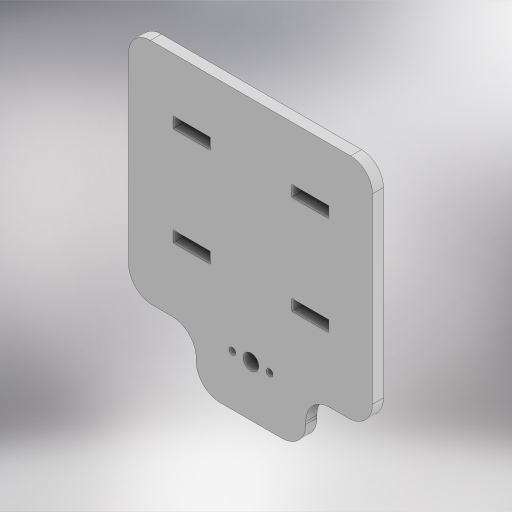
# Autodesk Inventor part: side
Saved by Autodesk Inventor 2023.5 (Build 275446000, 446)
## iProperties
Created: 2026-10-31
Part Number: side
Material: Generic
Document SubType Name: Modeling
Designer: WORKPLUS
Density: 1 g/cm^3
Appearance: Default
Author: WORKPLUS
Autodesk Inventor part; units mm, degrees
ref_plane "YZ Plane" through (0, 0, 0) normal (1, 0, 0) x (0, 1, 0)
ref_plane "XZ Plane" through (0, 0, 0) normal (0, 1, 0) x (-1, 0, 0)
ref_plane "XY Plane" through (0, 0, 0) normal (0, 0, 1) x (1, 0, 0)
sketch "Sketch1" plane through (0, 0, 0) normal (0, 0, 1) x (1, 0, 0)
  line L0 (-55.8711, -100) -> (55.3607, -100)
  line L1 (55.3607, -100) -> (55.3607, 27.1373)
  line L2 (-55.8711, 27.1373) -> (-55.8711, -100)
  line L3 (-35.4, -2.5) -> (35.4, -2.5)
  line L4 (35.4, -2.5) -> (35.4, 2.5)
  line L5 (35.4, 2.5) -> (-35.4, 2.5)
  line L6 (-35.4, 2.5) -> (-35.4, -2.5)
  line L7 (-35.4, 2.5) -> (-18.614, 2.5)
  line L8 (-18.614, 2.5) -> (-18.614, -2.5)
  line L9 (-18.614, -2.5) -> (-35.4, -2.5)
  line L10 (-35.4, -2.5) -> (-35.4, 2.5)
  line L11 (35.4, 2.5) -> (18.614, 2.5)
  line L12 (18.614, 2.5) -> (18.614, -2.5)
  line L13 (18.614, -2.5) -> (35.4, -2.5)
  line L14 (35.4, -2.5) -> (35.4, 2.5)
  line L15 (0, -2.5) -> (0, -42.5)
  line L16 (0, -42.5) -> (-35.4, -42.5)
  line L17 (0, -42.5) -> (35.4, -42.5)
  line L18 (-35.4, -42.5) -> (-35.4, -47.5)
  line L19 (-35.4, -47.5) -> (35.4, -47.5)
  line L20 (35.4, -47.5) -> (35.4, -42.5)
  line L21 (-18.614, -42.5) -> (-18.614, -47.5)
  line L22 (18.614, -42.5) -> (18.614, -47.5)
  line L23 (-55.8711, 27.1373) -> (55.3607, 27.1373)
  circle A0 centre (-8.5, -76.8807) radius 1.5
  circle A1 centre (8.5, -76.8807) radius 1.5
  circle A2 centre (0, -76.8807) radius 3.5
  circle A3 centre (0, -76.8807) radius 15
  line L24 (-55.8711, -76.8807) -> (-15, -76.8807)
  line L25 (15, -76.8807) -> (55.3607, -76.8807)
  line L26 (-25, -76.8807) -> (-25, -100)
  line L27 (25, -76.8807) -> (25, -100)
  dimension "d1" = 5
  dimension "d2" = 16.786
  dimension "d3" = 16.786
  dimension "d10" = 40
  dimension "d11" = 5
  dimension "d12" = 16.786
  dimension "d13" = 16.786
  dimension "d16" = 3
  dimension "d17" = 3
  dimension "d20" = 7
  dimension "d22" = 25
  dimension "d23" = 25
  dimension "d25" = 8.5
  dimension "d26" = 8.5
  constraints: 56 end point, 12 point on line, 11 perpendicular, 8 horizontal, 7 parallel, 4 centre point, 3 vertical, 2 point on circle, 1 coincident, 1 midpoint, 1 other
  measures "d1" distance of L3.end L4.end
  measures "d2" distance of L8.end L9.end
  measures "d3" distance of L13.end L12.end
  measures "d10" distance of L15.start L15.end
  measures "d11" distance of L16.end L18.end
  measures "d12" distance between parallel lines of L18 L21
  measures "d13" distance between parallel lines of L22 L20
  measures "d16" diameter of A0
  measures "d17" diameter of A1
  measures "d20" diameter of A2
  measures "d22" distance from line of L26 A3.centre
  measures "d23" distance from line of A2.centre L27
  measures "d25" distance of A2.centre A0.centre
  measures "d26" distance of A2.centre A1.centre
extrude "Extrusion1" add sketch "Sketch1" along normal blind 5 contours L26 L24 A3 L25 L27 L0 | L2 L23 L1 L25 A3 L24 | A3 | L17 L22 L19 L21 L16 | L8 L5 L12 L3
fillet "Fillet1" radius 11 6 edges at (-55.8711, -76.8807, 2.5) (-25, -76.8807, 2.5) (-25, -100, 2.5) (25, -100, 2.5) (55.3607, -76.8807, 2.5) (25, -76.8807, 2.5)
fillet "Fillet2" radius 10 2 edges at (55.3607, 27.1373, 2.5) (-55.8711, 27.1373, 2.5)
body "Solid1"
